Autodesk Fusion 360 part; units mm, degrees
(part 2 of 3)
sketch "Editable cross section (93)" plane through (0, 0, 0) normal (0, 0, 1) x (1, 0, 0) in component "right scoring bearing bridge 33"
  line L0 (-7.5, -5) -> (7.5, -5)
  line L1 (7.5, -5) -> (7.5, 5)
  line L2 (7.5, 5) -> (-7.5, 5)
  line L3 (-7.5, 5) -> (-7.5, -5)
extrude "Stock length''''''''''''''''''''''''''''''''''''''''''''''''''''''''''''''''''''''''''''''''''''''''''''" add sketch "Editable cross section (93)" along normal blind 42 separate body makes body 93 in component "right scoring bearing bridge 33"
sketch "Editable cross section (94)" plane through (0, 0, 0) normal (0, 0, 1) x (1, 0, 0) in component "left scoring wheel"
  circle A0 centre (0, 0) radius 32
extrude "Stock length'''''''''''''''''''''''''''''''''''''''''''''''''''''''''''''''''''''''''''''''''''''''''''''" add sketch "Editable cross section (94)" along normal blind 50 separate body makes body 94 in component "left scoring wheel"
sketch "Editable cross section (95)" plane through (0, 0, 0) normal (0, 0, 1) x (1, 0, 0) in component "left scoring spindle"
  circle A0 centre (0, 0) radius 6
extrude "Stock length''''''''''''''''''''''''''''''''''''''''''''''''''''''''''''''''''''''''''''''''''''''''''''''" add sketch "Editable cross section (95)" along normal blind 72 separate body makes body 95 in component "left scoring spindle"
sketch "Editable cross section (96)" plane through (0, 0, 0) normal (0, 0, 1) x (1, 0, 0) in component "left upper guide"
  line L0 (-3, -5) -> (3, -5)
  line L1 (3, -5) -> (3, 5)
  line L2 (3, 5) -> (-3, 5)
  line L3 (-3, 5) -> (-3, -5)
extrude "Stock length'''''''''''''''''''''''''''''''''''''''''''''''''''''''''''''''''''''''''''''''''''''''''''''''" add sketch "Editable cross section (96)" along normal blind 203.3249 separate body makes body 96 in component "left upper guide"
sketch "Editable cross section (97)" plane through (0, 0, 0) normal (0, 0, 1) x (1, 0, 0) in component "left scoring bearing bridge -33"
  line L0 (-7.5, -5) -> (7.5, -5)
  line L1 (7.5, -5) -> (7.5, 5)
  line L2 (7.5, 5) -> (-7.5, 5)
  line L3 (-7.5, 5) -> (-7.5, -5)
extrude "Stock length''''''''''''''''''''''''''''''''''''''''''''''''''''''''''''''''''''''''''''''''''''''''''''''''" add sketch "Editable cross section (97)" along normal blind 42 separate body makes body 97 in component "left scoring bearing bridge -33"
sketch "Editable cross section (98)" plane through (0, 0, 0) normal (0, 0, 1) x (1, 0, 0) in component "left scoring bearing bridge 33"
  line L0 (-7.5, -5) -> (7.5, -5)
  line L1 (7.5, -5) -> (7.5, 5)
  line L2 (7.5, 5) -> (-7.5, 5)
  line L3 (-7.5, 5) -> (-7.5, -5)
extrude "Stock length'''''''''''''''''''''''''''''''''''''''''''''''''''''''''''''''''''''''''''''''''''''''''''''''''" add sketch "Editable cross section (98)" along normal blind 42 separate body makes body 98 in component "left scoring bearing bridge 33"
sketch "Editable cross section (99)" plane through (0, 0, 0) normal (0, 0, 1) x (1, 0, 0) in component "left feed diverter pivot"
  circle A0 centre (0, 0) radius 7
extrude "Stock length''''''''''''''''''''''''''''''''''''''''''''''''''''''''''''''''''''''''''''''''''''''''''''''''''" add sketch "Editable cross section (99)" along normal blind 24 separate body makes body 99 in component "left feed diverter pivot"
sketch "Editable cross section (100)" plane through (0, 0, 0) normal (0, 0, 1) x (1, 0, 0) in component "right feed diverter pivot"
  circle A0 centre (0, 0) radius 7
extrude "Stock length'''''''''''''''''''''''''''''''''''''''''''''''''''''''''''''''''''''''''''''''''''''''''''''''''''" add sketch "Editable cross section (100)" along normal blind 24 separate body makes body 100 in component "right feed diverter pivot"
sketch "Editable cross section (101)" plane through (0, 0, 0) normal (0, 0, 1) x (1, 0, 0) in component "feed diverter vane"
  line L0 (-2, -75) -> (2, -75)
  line L1 (2, -75) -> (2, 75)
  line L2 (2, 75) -> (-2, 75)
  line L3 (-2, 75) -> (-2, -75)
extrude "Stock length''''''''''''''''''''''''''''''''''''''''''''''''''''''''''''''''''''''''''''''''''''''''''''''''''''" add sketch "Editable cross section (101)" along normal blind 46 separate body makes body 101 in component "feed diverter vane"
sketch "Editable cross section (102)" plane through (0, 0, 0) normal (0, 0, 1) x (1, 0, 0) in component "front left public wheel"
  circle A0 centre (0, 0) radius 38.1
extrude "Stock length'''''''''''''''''''''''''''''''''''''''''''''''''''''''''''''''''''''''''''''''''''''''''''''''''''''" add sketch "Editable cross section (102)" along normal blind 26 separate body makes body 102 in component "front left public wheel"
sketch "Editable cross section (103)" plane through (0, 0, 0) normal (0, 0, 1) x (1, 0, 0) in component "front left public drive housing"
  line L0 (-40, -40) -> (40, -40)
  line L1 (40, -40) -> (40, 40)
  line L2 (40, 40) -> (-40, 40)
  line L3 (-40, 40) -> (-40, -40)
extrude "Stock length''''''''''''''''''''''''''''''''''''''''''''''''''''''''''''''''''''''''''''''''''''''''''''''''''''''" add sketch "Editable cross section (103)" along normal blind 45 separate body makes body 103 in component "front left public drive housing"
sketch "Editable cross section (104)" plane through (0, 0, 0) normal (0, 0, 1) x (1, 0, 0) in component "front left public motor reserve"
  circle A0 centre (0, 0) radius 29.9
extrude "Stock length'''''''''''''''''''''''''''''''''''''''''''''''''''''''''''''''''''''''''''''''''''''''''''''''''''''''" add sketch "Editable cross section (104)" along normal blind 56.46 separate body makes body 104 in component "front left public motor reserve"
sketch "Editable cross section (105)" plane through (0, 0, 0) normal (0, 0, 1) x (1, 0, 0) in component "front right public wheel"
  circle A0 centre (0, 0) radius 38.1
extrude "Stock length''''''''''''''''''''''''''''''''''''''''''''''''''''''''''''''''''''''''''''''''''''''''''''''''''''''''" add sketch "Editable cross section (105)" along normal blind 26 separate body makes body 105 in component "front right public wheel"
sketch "Editable cross section (106)" plane through (0, 0, 0) normal (0, 0, 1) x (1, 0, 0) in component "front right public drive housing"
  line L0 (-40, -40) -> (40, -40)
  line L1 (40, -40) -> (40, 40)
  line L2 (40, 40) -> (-40, 40)
  line L3 (-40, 40) -> (-40, -40)
extrude "Stock length'''''''''''''''''''''''''''''''''''''''''''''''''''''''''''''''''''''''''''''''''''''''''''''''''''''''''" add sketch "Editable cross section (106)" along normal blind 45 separate body makes body 106 in component "front right public drive housing"
sketch "Editable cross section (107)" plane through (0, 0, 0) normal (0, 0, 1) x (1, 0, 0) in component "front right public motor reserve"
  circle A0 centre (0, 0) radius 29.9
extrude "Stock length''''''''''''''''''''''''''''''''''''''''''''''''''''''''''''''''''''''''''''''''''''''''''''''''''''''''''" add sketch "Editable cross section (107)" along normal blind 56.46 separate body makes body 107 in component "front right public motor reserve"
sketch "Editable cross section (108)" plane through (0, 0, 0) normal (0, 0, 1) x (1, 0, 0) in component "rear left public wheel"
  circle A0 centre (0, 0) radius 38.1
extrude "Stock length'''''''''''''''''''''''''''''''''''''''''''''''''''''''''''''''''''''''''''''''''''''''''''''''''''''''''''" add sketch "Editable cross section (108)" along normal blind 26 separate body makes body 108 in component "rear left public wheel"
sketch "Editable cross section (109)" plane through (0, 0, 0) normal (0, 0, 1) x (1, 0, 0) in component "rear left public drive housing"
  line L0 (-40, -40) -> (40, -40)
  line L1 (40, -40) -> (40, 40)
  line L2 (40, 40) -> (-40, 40)
  line L3 (-40, 40) -> (-40, -40)
extrude "Stock length''''''''''''''''''''''''''''''''''''''''''''''''''''''''''''''''''''''''''''''''''''''''''''''''''''''''''''" add sketch "Editable cross section (109)" along normal blind 45 separate body makes body 109 in component "rear left public drive housing"
sketch "Editable cross section (110)" plane through (0, 0, 0) normal (0, 0, 1) x (1, 0, 0) in component "rear left public motor reserve"
  circle A0 centre (0, 0) radius 29.9
extrude "Stock length'''''''''''''''''''''''''''''''''''''''''''''''''''''''''''''''''''''''''''''''''''''''''''''''''''''''''''''" add sketch "Editable cross section (110)" along normal blind 56.46 separate body makes body 110 in component "rear left public motor reserve"
sketch "Editable cross section (111)" plane through (0, 0, 0) normal (0, 0, 1) x (1, 0, 0) in component "rear right public wheel"
  circle A0 centre (0, 0) radius 38.1
extrude "Stock length''''''''''''''''''''''''''''''''''''''''''''''''''''''''''''''''''''''''''''''''''''''''''''''''''''''''''''''" add sketch "Editable cross section (111)" along normal blind 26 separate body makes body 111 in component "rear right public wheel"
sketch "Editable cross section (112)" plane through (0, 0, 0) normal (0, 0, 1) x (1, 0, 0) in component "rear right public drive housing"
  line L0 (-40, -40) -> (40, -40)
  line L1 (40, -40) -> (40, 40)
  line L2 (40, 40) -> (-40, 40)
  line L3 (-40, 40) -> (-40, -40)
extrude "Stock length'''''''''''''''''''''''''''''''''''''''''''''''''''''''''''''''''''''''''''''''''''''''''''''''''''''''''''''''" add sketch "Editable cross section (112)" along normal blind 45 separate body makes body 112 in component "rear right public drive housing"
sketch "Editable cross section (113)" plane through (0, 0, 0) normal (0, 0, 1) x (1, 0, 0) in component "rear right public motor reserve"
  circle A0 centre (0, 0) radius 29.9
extrude "Stock length''''''''''''''''''''''''''''''''''''''''''''''''''''''''''''''''''''''''''''''''''''''''''''''''''''''''''''''''" add sketch "Editable cross section (113)" along normal blind 56.46 separate body makes body 113 in component "rear right public motor reserve"
sketch "Editable cross section (114)" plane through (0, 0, 0) normal (0, 0, 1) x (1, 0, 0) in component "right public scoring motor envelope"
  circle A0 centre (0, 0) radius 30
extrude "Stock length'''''''''''''''''''''''''''''''''''''''''''''''''''''''''''''''''''''''''''''''''''''''''''''''''''''''''''''''''" add sketch "Editable cross section (114)" along normal blind 93.26 separate body makes body 114 in component "right public scoring motor envelope"
sketch "Editable cross section (115)" plane through (0, 0, 0) normal (0, 0, 1) x (1, 0, 0) in component "left public scoring motor envelope"
  circle A0 centre (0, 0) radius 30
extrude "Stock length''''''''''''''''''''''''''''''''''''''''''''''''''''''''''''''''''''''''''''''''''''''''''''''''''''''''''''''''''" add sketch "Editable cross section (115)" along normal blind 93.26 separate body makes body 115 in component "left public scoring motor envelope"
sketch "Editable cross section (116)" plane through (0, 0, 0) normal (0, 0, 1) x (1, 0, 0) in component "rear lift custody gate"
  line L0 (-2, -65) -> (2, -65)
  line L1 (2, -65) -> (2, 65)
  line L2 (2, 65) -> (-2, 65)
  line L3 (-2, 65) -> (-2, -65)
extrude "Stock length'''''''''''''''''''''''''''''''''''''''''''''''''''''''''''''''''''''''''''''''''''''''''''''''''''''''''''''''''''" add sketch "Editable cross section (116)" along normal blind 416 separate body makes body 116 in component "rear lift custody gate"
sketch "Editable cross section (117)" plane through (0, 0, 0) normal (0, 0, 1) x (1, 0, 0) in component "front lift custody guide"
  line L0 (-2, -65) -> (2, -65)
  line L1 (2, -65) -> (2, 65)
  line L2 (2, 65) -> (-2, 65)
  line L3 (-2, 65) -> (-2, -65)
extrude "Stock length''''''''''''''''''''''''''''''''''''''''''''''''''''''''''''''''''''''''''''''''''''''''''''''''''''''''''''''''''''" add sketch "Editable cross section (117)" along normal blind 361 separate body makes body 117 in component "front lift custody guide"
sketch "Editable cross section (118)" plane through (0, 0, 0) normal (0, 0, 1) x (1, 0, 0) in component "left mast"
  line L0 (-10, -10) -> (10, -10)
  line L1 (10, -10) -> (10, 10)
  line L2 (10, 10) -> (-10, 10)
  line L3 (-10, 10) -> (-10, -10)
  line L4 (-8, -8) -> (8, -8)
  line L5 (8, -8) -> (8, 8)
  line L6 (8, 8) -> (-8, 8)
  line L7 (-8, 8) -> (-8, -8)
extrude "Stock length'''''''''''''''''''''''''''''''''''''''''''''''''''''''''''''''''''''''''''''''''''''''''''''''''''''''''''''''''''''" add sketch "Editable cross section (118)" along normal blind 629.2 separate body makes body 118 in component "left mast"
sketch "Editable cross section (119)" plane through (0, 0, 0) normal (0, 0, 1) x (1, 0, 0) in component "left aft mast"
  line L0 (-10, -10) -> (10, -10)
  line L1 (10, -10) -> (10, 10)
  line L2 (10, 10) -> (-10, 10)
  line L3 (-10, 10) -> (-10, -10)
  line L4 (-8, -8) -> (8, -8)
  line L5 (8, -8) -> (8, 8)
  line L6 (8, 8) -> (-8, 8)
  line L7 (-8, 8) -> (-8, -8)
extrude "Stock length''''''''''''''''''''''''''''''''''''''''''''''''''''''''''''''''''''''''''''''''''''''''''''''''''''''''''''''''''''''" add sketch "Editable cross section (119)" along normal blind 629.2 separate body makes body 119 in component "left aft mast"
sketch "Editable cross section (120)" plane through (0, 0, 0) normal (0, 0, 1) x (1, 0, 0) in component "left upper bearing plate"
  line L0 (-64, -19) -> (64, -19)
  line L1 (64, -19) -> (64, 19)
  line L2 (64, 19) -> (-64, 19)
  line L3 (-64, 19) -> (-64, -19)
extrude "Stock length'''''''''''''''''''''''''''''''''''''''''''''''''''''''''''''''''''''''''''''''''''''''''''''''''''''''''''''''''''''''" add sketch "Editable cross section (120)" along normal blind 6 separate body makes body 120 in component "left upper bearing plate"
sketch "Editable cross section (121)" plane through (0, 0, 0) normal (0, 0, 1) x (1, 0, 0) in component "left lower bearing plate"
  line L0 (-27, -21.5) -> (27, -21.5)
  line L1 (27, -21.5) -> (27, 21.5)
  line L2 (27, 21.5) -> (-27, 21.5)
  line L3 (-27, 21.5) -> (-27, -21.5)
extrude "Stock length''''''''''''''''''''''''''''''''''''''''''''''''''''''''''''''''''''''''''''''''''''''''''''''''''''''''''''''''''''''''" add sketch "Editable cross section (121)" along normal blind 6 separate body makes body 121 in component "left lower bearing plate"
sketch "Editable cross section (122)" plane through (0, 0, 0) normal (0, 0, 1) x (1, 0, 0) in component "left lead screw envelope"
  circle A0 centre (0, 0) radius 5
extrude "Stock length'''''''''''''''''''''''''''''''''''''''''''''''''''''''''''''''''''''''''''''''''''''''''''''''''''''''''''''''''''''''''" add sketch "Editable cross section (122)" along normal blind 187 separate body makes body 122 in component "left lead screw envelope"
sketch "Editable cross section (123)" plane through (0, 0, 0) normal (0, 0, 1) x (1, 0, 0) in component "left lift motor envelope"
  circle A0 centre (0, 0) radius 30
extrude "Stock length''''''''''''''''''''''''''''''''''''''''''''''''''''''''''''''''''''''''''''''''''''''''''''''''''''''''''''''''''''''''''" add sketch "Editable cross section (123)" along normal blind 61 separate body makes body 123 in component "left lift motor envelope"
sketch "Editable cross section (124)" plane through (0, 0, 0) normal (0, 0, 1) x (1, 0, 0) in component "left reduction envelope"
  line L0 (-19, -32) -> (19, -32)
  line L1 (19, -32) -> (19, 32)
  line L2 (19, 32) -> (-19, 32)
  line L3 (-19, 32) -> (-19, -32)
extrude "Stock length'''''''''''''''''''''''''''''''''''''''''''''''''''''''''''''''''''''''''''''''''''''''''''''''''''''''''''''''''''''''''''" add sketch "Editable cross section (124)" along normal blind 20 separate body makes body 124 in component "left reduction envelope"
sketch "Editable cross section (125)" plane through (0, 0, 0) normal (0, 0, 1) x (1, 0, 0) in component "left driven nut"
  line L0 (-9, -9.5) -> (9, -9.5)
  line L1 (9, -9.5) -> (9, 9.5)
  line L2 (9, 9.5) -> (-9, 9.5)
  line L3 (-9, 9.5) -> (-9, -9.5)
  circle A0 centre (0, -0.5) radius 5
extrude "Stock length''''''''''''''''''''''''''''''''''''''''''''''''''''''''''''''''''''''''''''''''''''''''''''''''''''''''''''''''''''''''''''" add sketch "Editable cross section (125)" along normal blind 14 separate body makes body 125 in component "left driven nut"
sketch "Editable cross section (126)" plane through (0, 0, 0) normal (0, 0, 1) x (1, 0, 0) in component "left nut link"
  line L0 (-8, -8) -> (8, -8)
  line L1 (8, -8) -> (8, 8)
  line L2 (8, 8) -> (-8, 8)
  line L3 (-8, 8) -> (-8, -8)
  circle A0 centre (0, -1) radius 5.8
extrude "Stock length'''''''''''''''''''''''''''''''''''''''''''''''''''''''''''''''''''''''''''''''''''''''''''''''''''''''''''''''''''''''''''''" add sketch "Editable cross section (126)" along normal blind 10 separate body makes body 126 in component "left nut link"
sketch "Editable cross section (127)" plane through (0, 0, 0) normal (0, 0, 1) x (1, 0, 0) in component "left crosshead cheek"
  line L0 (-87.5, -11.5) -> (87.5, -11.5)
  line L1 (87.5, -11.5) -> (87.5, 11.5)
  line L2 (87.5, 11.5) -> (-87.5, 11.5)
  line L3 (-87.5, 11.5) -> (-87.5, -11.5)
  circle A0 centre (-35.5, 1.5) radius 5.8
extrude "Stock length''''''''''''''''''''''''''''''''''''''''''''''''''''''''''''''''''''''''''''''''''''''''''''''''''''''''''''''''''''''''''''''" add sketch "Editable cross section (127)" along normal blind 14 separate body makes body 127 in component "left crosshead cheek"
sketch "Editable cross section (128)" plane through (0, 0, 0) normal (0, 0, 1) x (1, 0, 0) in component "left forward carriage sleeve"
  line L0 (-13, -12.5) -> (13, -12.5)
  line L1 (13, -12.5) -> (13, 12.5)
  line L2 (13, 12.5) -> (-13, 12.5)
  line L3 (-13, 12.5) -> (-13, -12.5)
  line L4 (-11, -10.5) -> (11, -10.5)
  line L5 (11, -10.5) -> (11, 10.5)
  line L6 (11, 10.5) -> (-11, 10.5)
  line L7 (-11, 10.5) -> (-11, -10.5)
extrude "Stock length'''''''''''''''''''''''''''''''''''''''''''''''''''''''''''''''''''''''''''''''''''''''''''''''''''''''''''''''''''''''''''''''" add sketch "Editable cross section (128)" along normal blind 40 separate body makes body 128 in component "left forward carriage sleeve"
sketch "Editable cross section (129)" plane through (0, 0, 0) normal (0, 0, 1) x (1, 0, 0) in component "left aft carriage sleeve"
  line L0 (-13, -12.5) -> (13, -12.5)
  line L1 (13, -12.5) -> (13, 12.5)
  line L2 (13, 12.5) -> (-13, 12.5)
  line L3 (-13, 12.5) -> (-13, -12.5)
  line L4 (-11, -10.5) -> (11, -10.5)
  line L5 (11, -10.5) -> (11, 10.5)
  line L6 (11, 10.5) -> (-11, 10.5)
  line L7 (-11, 10.5) -> (-11, -10.5)
extrude "Stock length''''''''''''''''''''''''''''''''''''''''''''''''''''''''''''''''''''''''''''''''''''''''''''''''''''''''''''''''''''''''''''''''" add sketch "Editable cross section (129)" along normal blind 40 separate body makes body 129 in component "left aft carriage sleeve"
sketch "Editable cross section (130)" plane through (0, 0, 0) normal (0, 0, 1) x (1, 0, 0) in component "left extension sleeve"
  line L0 (-14, -15) -> (14, -15)
  line L1 (14, -15) -> (14, 15)
  line L2 (14, 15) -> (-14, 15)
  line L3 (-14, 15) -> (-14, -15)
  line L4 (-12, -13) -> (12, -13)
  line L5 (12, -13) -> (12, 13)
  line L6 (12, 13) -> (-12, 13)
  line L7 (-12, 13) -> (-12, -13)
extrude "Stock length'''''''''''''''''''''''''''''''''''''''''''''''''''''''''''''''''''''''''''''''''''''''''''''''''''''''''''''''''''''''''''''''''" add sketch "Editable cross section (130)" along normal blind 87 separate body makes body 130 in component "left extension sleeve"
sketch "Editable cross section (131)" plane through (0, 0, 0) normal (0, 0, 1) x (1, 0, 0) in component "left sleeve pedestal"
  line L0 (-11, -11) -> (11, -11)
  line L1 (11, -11) -> (11, 11)
  line L2 (11, 11) -> (-11, 11)
  line L3 (-11, 11) -> (-11, -11)
extrude "Stock length''''''''''''''''''''''''''''''''''''''''''''''''''''''''''''''''''''''''''''''''''''''''''''''''''''''''''''''''''''''''''''''''''" add sketch "Editable cross section (131)" along normal blind 23 separate body makes body 131 in component "left sleeve pedestal"
sketch "Editable cross section (132)" plane through (0, 0, 0) normal (0, 0, 1) x (1, 0, 0) in component "left extending rail"
  line L0 (-10, -11) -> (10, -11)
  line L1 (10, -11) -> (10, 11)
  line L2 (10, 11) -> (-10, 11)
  line L3 (-10, 11) -> (-10, -11)
  line L4 (-8, -9) -> (8, -9)
  line L5 (8, -9) -> (8, 9)
  line L6 (8, 9) -> (-8, 9)
  line L7 (-8, 9) -> (-8, -9)
extrude "Stock length'''''''''''''''''''''''''''''''''''''''''''''''''''''''''''''''''''''''''''''''''''''''''''''''''''''''''''''''''''''''''''''''''''" add sketch "Editable cross section (132)" along normal blind 395 separate body makes body 132 in component "left extending rail"
sketch "Low-rung crown and capture slot" plane through (0, 0, 0) normal (0, 0, 1) x (1, 0, 0) in component "left crown hook"
  line L0 (-283, 710) -> (-271, 710)
  line L1 (-271, 710) -> (-271, 737)
  line L2 (-271, 737) -> (-223, 737)
  line L3 (-223, 737) -> (-223, 710)
  line L4 (-223, 710) -> (-211, 710)
  line L5 (-211, 710) -> (-211, 736)
  line L6 (-211, 736) -> (-176, 736)
  line L7 (-176, 736) -> (-176, 753)
  line L8 (-176, 753) -> (-283, 753)
  line L9 (-283, 753) -> (-283, 710)
extrude "Hook plate thickness" add sketch "Low-rung crown and capture slot" along normal blind 12 separate body makes body 133 in component "left crown hook"
sketch "Editable cross section (133)" plane through (0, 0, 0) normal (0, 0, 1) x (1, 0, 0) in component "right mast"
  line L0 (-10, -10) -> (10, -10)
  line L1 (10, -10) -> (10, 10)
  line L2 (10, 10) -> (-10, 10)
  line L3 (-10, 10) -> (-10, -10)
  line L4 (-8, -8) -> (8, -8)
  line L5 (8, -8) -> (8, 8)
  line L6 (8, 8) -> (-8, 8)
  line L7 (-8, 8) -> (-8, -8)
extrude "Stock length''''''''''''''''''''''''''''''''''''''''''''''''''''''''''''''''''''''''''''''''''''''''''''''''''''''''''''''''''''''''''''''''''''" add sketch "Editable cross section (133)" along normal blind 629.2 separate body makes body 134 in component "right mast"
sketch "Editable cross section (134)" plane through (0, 0, 0) normal (0, 0, 1) x (1, 0, 0) in component "right aft mast"
  line L0 (-10, -10) -> (10, -10)
  line L1 (10, -10) -> (10, 10)
  line L2 (10, 10) -> (-10, 10)
  line L3 (-10, 10) -> (-10, -10)
  line L4 (-8, -8) -> (8, -8)
  line L5 (8, -8) -> (8, 8)
  line L6 (8, 8) -> (-8, 8)
  line L7 (-8, 8) -> (-8, -8)
extrude "Stock length'''''''''''''''''''''''''''''''''''''''''''''''''''''''''''''''''''''''''''''''''''''''''''''''''''''''''''''''''''''''''''''''''''''" add sketch "Editable cross section (134)" along normal blind 629.2 separate body makes body 135 in component "right aft mast"
sketch "Editable cross section (135)" plane through (0, 0, 0) normal (0, 0, 1) x (1, 0, 0) in component "right upper bearing plate"
  line L0 (-64, -19) -> (64, -19)
  line L1 (64, -19) -> (64, 19)
  line L2 (64, 19) -> (-64, 19)
  line L3 (-64, 19) -> (-64, -19)
extrude "Stock length''''''''''''''''''''''''''''''''''''''''''''''''''''''''''''''''''''''''''''''''''''''''''''''''''''''''''''''''''''''''''''''''''''''" add sketch "Editable cross section (135)" along normal blind 6 separate body makes body 136 in component "right upper bearing plate"
sketch "Editable cross section (136)" plane through (0, 0, 0) normal (0, 0, 1) x (1, 0, 0) in component "right lower bearing plate"
  line L0 (-27, -21.5) -> (27, -21.5)
  line L1 (27, -21.5) -> (27, 21.5)
  line L2 (27, 21.5) -> (-27, 21.5)
  line L3 (-27, 21.5) -> (-27, -21.5)
extrude "Stock length'''''''''''''''''''''''''''''''''''''''''''''''''''''''''''''''''''''''''''''''''''''''''''''''''''''''''''''''''''''''''''''''''''''''" add sketch "Editable cross section (136)" along normal blind 6 separate body makes body 137 in component "right lower bearing plate"
sketch "Editable cross section (137)" plane through (0, 0, 0) normal (0, 0, 1) x (1, 0, 0) in component "right lead screw envelope"
  circle A0 centre (0, 0) radius 5
extrude "Stock length''''''''''''''''''''''''''''''''''''''''''''''''''''''''''''''''''''''''''''''''''''''''''''''''''''''''''''''''''''''''''''''''''''''''" add sketch "Editable cross section (137)" along normal blind 187 separate body makes body 138 in component "right lead screw envelope"
sketch "Editable cross section (138)" plane through (0, 0, 0) normal (0, 0, 1) x (1, 0, 0) in component "right lift motor envelope"
  circle A0 centre (0, 0) radius 30
extrude "Stock length'''''''''''''''''''''''''''''''''''''''''''''''''''''''''''''''''''''''''''''''''''''''''''''''''''''''''''''''''''''''''''''''''''''''''" add sketch "Editable cross section (138)" along normal blind 61 separate body makes body 139 in component "right lift motor envelope"
sketch "Editable cross section (139)" plane through (0, 0, 0) normal (0, 0, 1) x (1, 0, 0) in component "right reduction envelope"
  line L0 (-19, -32) -> (19, -32)
  line L1 (19, -32) -> (19, 32)
  line L2 (19, 32) -> (-19, 32)
  line L3 (-19, 32) -> (-19, -32)
extrude "Stock length''''''''''''''''''''''''''''''''''''''''''''''''''''''''''''''''''''''''''''''''''''''''''''''''''''''''''''''''''''''''''''''''''''''''''" add sketch "Editable cross section (139)" along normal blind 20 separate body makes body 140 in component "right reduction envelope"
sketch "Editable cross section (140)" plane through (0, 0, 0) normal (0, 0, 1) x (1, 0, 0) in component "right driven nut"
  line L0 (-9, -9.5) -> (9, -9.5)
  line L1 (9, -9.5) -> (9, 9.5)
  line L2 (9, 9.5) -> (-9, 9.5)
  line L3 (-9, 9.5) -> (-9, -9.5)
  circle A0 centre (0, 0.5) radius 5
extrude "Stock length'''''''''''''''''''''''''''''''''''''''''''''''''''''''''''''''''''''''''''''''''''''''''''''''''''''''''''''''''''''''''''''''''''''''''''" add sketch "Editable cross section (140)" along normal blind 14 separate body makes body 141 in component "right driven nut"
sketch "Editable cross section (141)" plane through (0, 0, 0) normal (0, 0, 1) x (1, 0, 0) in component "right nut link"
  line L0 (-8, -8) -> (8, -8)
  line L1 (8, -8) -> (8, 8)
  line L2 (8, 8) -> (-8, 8)
  line L3 (-8, 8) -> (-8, -8)
  circle A0 centre (0, 1) radius 5.8
extrude "Stock length''''''''''''''''''''''''''''''''''''''''''''''''''''''''''''''''''''''''''''''''''''''''''''''''''''''''''''''''''''''''''''''''''''''''''''" add sketch "Editable cross section (141)" along normal blind 10 separate body makes body 142 in component "right nut link"
sketch "Editable cross section (142)" plane through (0, 0, 0) normal (0, 0, 1) x (1, 0, 0) in component "right crosshead cheek"
  line L0 (-87.5, -11.5) -> (87.5, -11.5)
  line L1 (87.5, -11.5) -> (87.5, 11.5)
  line L2 (87.5, 11.5) -> (-87.5, 11.5)
  line L3 (-87.5, 11.5) -> (-87.5, -11.5)
  circle A0 centre (-35.5, -1.5) radius 5.8
extrude "Stock length'''''''''''''''''''''''''''''''''''''''''''''''''''''''''''''''''''''''''''''''''''''''''''''''''''''''''''''''''''''''''''''''''''''''''''''" add sketch "Editable cross section (142)" along normal blind 14 separate body makes body 143 in component "right crosshead cheek"
sketch "Editable cross section (143)" plane through (0, 0, 0) normal (0, 0, 1) x (1, 0, 0) in component "right forward carriage sleeve"
  line L0 (-13, -12.5) -> (13, -12.5)
  line L1 (13, -12.5) -> (13, 12.5)
  line L2 (13, 12.5) -> (-13, 12.5)
  line L3 (-13, 12.5) -> (-13, -12.5)
  line L4 (-11, -10.5) -> (11, -10.5)
  line L5 (11, -10.5) -> (11, 10.5)
  line L6 (11, 10.5) -> (-11, 10.5)
  line L7 (-11, 10.5) -> (-11, -10.5)
extrude "Stock length''''''''''''''''''''''''''''''''''''''''''''''''''''''''''''''''''''''''''''''''''''''''''''''''''''''''''''''''''''''''''''''''''''''''''''''" add sketch "Editable cross section (143)" along normal blind 40 separate body makes body 144 in component "right forward carriage sleeve"
sketch "Editable cross section (144)" plane through (0, 0, 0) normal (0, 0, 1) x (1, 0, 0) in component "right aft carriage sleeve"
  line L0 (-13, -12.5) -> (13, -12.5)
  line L1 (13, -12.5) -> (13, 12.5)
  line L2 (13, 12.5) -> (-13, 12.5)
  line L3 (-13, 12.5) -> (-13, -12.5)
  line L4 (-11, -10.5) -> (11, -10.5)
  line L5 (11, -10.5) -> (11, 10.5)
  line L6 (11, 10.5) -> (-11, 10.5)
  line L7 (-11, 10.5) -> (-11, -10.5)
extrude "Stock length'''''''''''''''''''''''''''''''''''''''''''''''''''''''''''''''''''''''''''''''''''''''''''''''''''''''''''''''''''''''''''''''''''''''''''''''" add sketch "Editable cross section (144)" along normal blind 40 separate body makes body 145 in component "right aft carriage sleeve"
sketch "Editable cross section (145)" plane through (0, 0, 0) normal (0, 0, 1) x (1, 0, 0) in component "right extension sleeve"
  line L0 (-14, -15) -> (14, -15)
  line L1 (14, -15) -> (14, 15)
  line L2 (14, 15) -> (-14, 15)
  line L3 (-14, 15) -> (-14, -15)
  line L4 (-12, -13) -> (12, -13)
  line L5 (12, -13) -> (12, 13)
  line L6 (12, 13) -> (-12, 13)
  line L7 (-12, 13) -> (-12, -13)
extrude "Stock length''''''''''''''''''''''''''''''''''''''''''''''''''''''''''''''''''''''''''''''''''''''''''''''''''''''''''''''''''''''''''''''''''''''''''''''''" add sketch "Editable cross section (145)" along normal blind 87 separate body makes body 146 in component "right extension sleeve"
sketch "Editable cross section (146)" plane through (0, 0, 0) normal (0, 0, 1) x (1, 0, 0) in component "right sleeve pedestal"
  line L0 (-11, -11) -> (11, -11)
  line L1 (11, -11) -> (11, 11)
  line L2 (11, 11) -> (-11, 11)
  line L3 (-11, 11) -> (-11, -11)
extrude "Stock length'''''''''''''''''''''''''''''''''''''''''''''''''''''''''''''''''''''''''''''''''''''''''''''''''''''''''''''''''''''''''''''''''''''''''''''''''" add sketch "Editable cross section (146)" along normal blind 23 separate body makes body 147 in component "right sleeve pedestal"
sketch "Editable cross section (147)" plane through (0, 0, 0) normal (0, 0, 1) x (1, 0, 0) in component "right extending rail"
  line L0 (-10, -11) -> (10, -11)
  line L1 (10, -11) -> (10, 11)
  line L2 (10, 11) -> (-10, 11)
  line L3 (-10, 11) -> (-10, -11)
  line L4 (-8, -9) -> (8, -9)
  line L5 (8, -9) -> (8, 9)
  line L6 (8, 9) -> (-8, 9)
  line L7 (-8, 9) -> (-8, -9)
extrude "Stock length''''''''''''''''''''''''''''''''''''''''''''''''''''''''''''''''''''''''''''''''''''''''''''''''''''''''''''''''''''''''''''''''''''''''''''''''''" add sketch "Editable cross section (147)" along normal blind 395 separate body makes body 148 in component "right extending rail"
sketch "Low-rung crown and capture slot (2)" plane through (0, 0, 0) normal (0, 0, 1) x (1, 0, 0) in component "right crown hook"
  line L0 (-283, 710) -> (-271, 710)
  line L1 (-271, 710) -> (-271, 737)
  line L2 (-271, 737) -> (-223, 737)
  line L3 (-223, 737) -> (-223, 710)
  line L4 (-223, 710) -> (-211, 710)
  line L5 (-211, 710) -> (-211, 736)
  line L6 (-211, 736) -> (-176, 736)
  line L7 (-176, 736) -> (-176, 753)
  line L8 (-176, 753) -> (-283, 753)
  line L9 (-283, 753) -> (-283, 710)
extrude "Hook plate thickness'" add sketch "Low-rung crown and capture slot (2)" along normal blind 12 separate body makes body 149 in component "right crown hook"
sketch "Editable cross section (148)" plane through (0, 0, 0) normal (0, 0, 1) x (1, 0, 0) in component "crosshead lift bridge"
  line L0 (-10, -10) -> (10, -10)
  line L1 (10, -10) -> (10, 10)
  line L2 (10, 10) -> (-10, 10)
  line L3 (-10, 10) -> (-10, -10)
  line L4 (-8, -8) -> (8, -8)
  line L5 (8, -8) -> (8, 8)
  line L6 (8, 8) -> (-8, 8)
  line L7 (-8, 8) -> (-8, -8)
extrude "Stock length'''''''''''''''''''''''''''''''''''''''''''''''''''''''''''''''''''''''''''''''''''''''''''''''''''''''''''''''''''''''''''''''''''''''''''''''''''" add sketch "Editable cross section (148)" along normal blind 630 separate body makes body 150 in component "crosshead lift bridge"
sketch "Editable cross section (149)" plane through (0, 0, 0) normal (0, 0, 1) x (1, 0, 0) in component "rail synchronizing tie"
  line L0 (-10, -82) -> (10, -82)
  line L1 (10, -82) -> (10, 82)
  line L2 (10, 82) -> (-10, 82)
  line L3 (-10, 82) -> (-10, -82)
extrude "Stock length''''''''''''''''''''''''''''''''''''''''''''''''''''''''''''''''''''''''''''''''''''''''''''''''''''''''''''''''''''''''''''''''''''''''''''''''''''" add sketch "Editable cross section (149)" along normal blind 4 separate body makes body 151 in component "rail synchronizing tie"
sketch "Editable cross section (150)" plane through (0, 0, 0) normal (0, 0, 1) x (1, 0, 0) in component "extension bearing beam"
  line L0 (-193, -14) -> (193, -14)
  line L1 (193, -14) -> (193, 14)
  line L2 (193, 14) -> (-193, 14)
  line L3 (-193, 14) -> (-193, -14)
extrude "Stock length'''''''''''''''''''''''''''''''''''''''''''''''''''''''''''''''''''''''''''''''''''''''''''''''''''''''''''''''''''''''''''''''''''''''''''''''''''''" add sketch "Editable cross section (150)" along normal blind 15 separate body makes body 152 in component "extension bearing beam"
sketch "Editable cross section (151)" plane through (0, 0, 0) normal (0, 0, 1) x (1, 0, 0) in component "extension rear bearing and stop"
  line L0 (-14, -17) -> (14, -17)
  line L1 (14, -17) -> (14, 17)
  line L2 (14, 17) -> (-14, 17)
  line L3 (-14, 17) -> (-14, -17)
  circle A0 centre (0, 0) radius 5.2
extrude "Stock length''''''''''''''''''''''''''''''''''''''''''''''''''''''''''''''''''''''''''''''''''''''''''''''''''''''''''''''''''''''''''''''''''''''''''''''''''''''" add sketch "Editable cross section (151)" along normal blind 12 separate body makes body 153 in component "extension rear bearing and stop"
sketch "Editable cross section (152)" plane through (0, 0, 0) normal (0, 0, 1) x (1, 0, 0) in component "extension forward bearing"
  line L0 (-14, -17) -> (14, -17)
  line L1 (14, -17) -> (14, 17)
  line L2 (14, 17) -> (-14, 17)
  line L3 (-14, 17) -> (-14, -17)
  circle A0 centre (0, 0) radius 5.2
extrude "Stock length'''''''''''''''''''''''''''''''''''''''''''''''''''''''''''''''''''''''''''''''''''''''''''''''''''''''''''''''''''''''''''''''''''''''''''''''''''''''" add sketch "Editable cross section (152)" along normal blind 12 separate body makes body 154 in component "extension forward bearing"
sketch "Editable cross section (153)" plane through (0, 0, 0) normal (0, 0, 1) x (1, 0, 0) in component "extension screw envelope"
  circle A0 centre (0, 0) radius 5
extrude "Stock length''''''''''''''''''''''''''''''''''''''''''''''''''''''''''''''''''''''''''''''''''''''''''''''''''''''''''''''''''''''''''''''''''''''''''''''''''''''''" add sketch "Editable cross section (153)" along normal blind 279 separate body makes body 155 in component "extension screw envelope"
sketch "Editable cross section (154)" plane through (0, 0, 0) normal (0, 0, 1) x (1, 0, 0) in component "extension deployment nut"
  line L0 (-10, -13) -> (10, -13)
  line L1 (10, -13) -> (10, 13)
  line L2 (10, 13) -> (-10, 13)
  line L3 (-10, 13) -> (-10, -13)
  circle A0 centre (0, 0) radius 5
extrude "Stock length'''''''''''''''''''''''''''''''''''''''''''''''''''''''''''''''''''''''''''''''''''''''''''''''''''''''''''''''''''''''''''''''''''''''''''''''''''''''''" add sketch "Editable cross section (154)" along normal blind 20 separate body makes body 156 in component "extension deployment nut"
sketch "Editable cross section (155)" plane through (0, 0, 0) normal (0, 0, 1) x (1, 0, 0) in component "extension nut hanger"
  line L0 (-10, -8) -> (10, -8)
  line L1 (10, -8) -> (10, 8)
  line L2 (10, 8) -> (-10, 8)
  line L3 (-10, 8) -> (-10, -8)
extrude "Stock length''''''''''''''''''''''''''''''''''''''''''''''''''''''''''''''''''''''''''''''''''''''''''''''''''''''''''''''''''''''''''''''''''''''''''''''''''''''''''" add sketch "Editable cross section (155)" along normal blind 4 separate body makes body 157 in component "extension nut hanger"
sketch "Editable cross section (156)" plane through (0, 0, 0) normal (0, 0, 1) x (1, 0, 0) in component "extension motor envelope"
  circle A0 centre (0, 0) radius 18
extrude "Stock length'''''''''''''''''''''''''''''''''''''''''''''''''''''''''''''''''''''''''''''''''''''''''''''''''''''''''''''''''''''''''''''''''''''''''''''''''''''''''''" add sketch "Editable cross section (156)" along normal blind 49 separate body makes body 158 in component "extension motor envelope"
sketch "Editable cross section (157)" plane through (0, 0, 0) normal (0, 0, 1) x (1, 0, 0) in component "extension motor foot"
  line L0 (-8, -9) -> (8, -9)
  line L1 (8, -9) -> (8, 9)
  line L2 (8, 9) -> (-8, 9)
  line L3 (-8, 9) -> (-8, -9)
extrude "Stock length''''''''''''''''''''''''''''''''''''''''''''''''''''''''''''''''''''''''''''''''''''''''''''''''''''''''''''''''''''''''''''''''''''''''''''''''''''''''''''" add sketch "Editable cross section (157)" along normal blind 2 separate body makes body 159 in component "extension motor foot"
component "left perimeter tube" placed x (0, 1, 0) y (0, 0, 1) z (1, 0, 0) at (-340, 327.3, 89.4)
component "left front return" placed x (-1, 0, 0) y (0, 0, 1) z (0, 1, 0) at (327.3, 150, 89.4)
component "left blue side bumper" placed x (1, 0, 0) y (0, 1, 0) z (0, 0, 1) at (0, 378, 48)
component "left blue front bumper" placed x (1, 0, 0) y (0, 1, 0) z (0, 0, 1) at (378, 245, 48)
component "right perimeter tube" placed x (0, 1, 0) y (0, 0, 1) z (1, 0, 0) at (-340, -327.3, 89.4)
component "right front return" placed x (-1, 0, 0) y (0, 0, 1) z (0, 1, 0) at (327.3, -314.6, 89.4)
component "right blue side bumper" placed x (1, 0, 0) y (0, 1, 0) z (0, 0, 1) at (0, -378, 48)
component "right blue front bumper" placed x (1, 0, 0) y (0, 1, 0) z (0, 0, 1) at (378, -245, 48)
component "rear perimeter tube" placed x (-1, 0, 0) y (0, 0, 1) z (0, 1, 0) at (-327.3, -314.6, 89.4)
component "rear blue bumper" placed x (1, 0, 0) y (0, 1, 0) z (0, 0, 1) at (-378, 0, 48)
component "front left module tab spacer 1" placed x (1, 0, 0) y (0, 1, 0) z (0, 0, 1) at (198, 303.05, 78.32)
component "front left module tab spacer 2" placed x (1, 0, 0) y (0, 1, 0) z (0, 0, 1) at (303.05, 198, 78.32)
component "front right module tab spacer 1" placed x (1, 0, 0) y (0, 1, 0) z (0, 0, 1) at (303.05, -198, 78.32)
component "front right module tab spacer 2" placed x (1, 0, 0) y (0, 1, 0) z (0, 0, 1) at (198, -303.05, 78.32)
component "rear left module tab spacer 1" placed x (1, 0, 0) y (0, 1, 0) z (0, 0, 1) at (-303.05, 198, 78.32)
component "rear left module tab spacer 2" placed x (1, 0, 0) y (0, 1, 0) z (0, 0, 1) at (-198, 303.05, 78.32)
component "rear right module tab spacer 1" placed x (1, 0, 0) y (0, 1, 0) z (0, 0, 1) at (-198, -303.05, 78.32)
component "rear right module tab spacer 2" placed x (1, 0, 0) y (0, 1, 0) z (0, 0, 1) at (-303.05, -198, 78.32)
component "rear right hopper post" placed x (1, 0, 0) y (0, 1, 0) z (0, 0, 1) at (-188, -306, 115)
component "front right hopper post" placed x (1, 0, 0) y (0, 1, 0) z (0, 0, 1) at (176, -306, 115)
component "right floor sill" placed x (0, 1, 0) y (0, 0, 1) z (1, 0, 0) at (-330, -306, 227)
component "rear left hopper post" placed x (1, 0, 0) y (0, 1, 0) z (0, 0, 1) at (-188, 306, 115)
component "front left hopper post" placed x (1, 0, 0) y (0, 1, 0) z (0, 0, 1) at (176, 306, 115)
component "left floor sill" placed x (0, 1, 0) y (0, 0, 1) z (1, 0, 0) at (-330, 306, 227)
component "rear deck crossmember" placed x (-1, 0, 0) y (0, 0, 1) z (0, 1, 0) at (-188, -315, 113)
component "front deck crossmember" placed x (-1, 0, 0) y (0, 0, 1) z (0, 1, 0) at (176, -315, 113)
component "left electronics deck" placed x (1, 0, 0) y (0, 1, 0) z (0, 0, 1) at (-5.5, 149, 122)
component "right electronics deck" placed x (1, 0, 0) y (0, 1, 0) z (0, 0, 1) at (-5.5, -147.5, 122)
component "fore electronics deck bridge" placed x (1, 0, 0) y (0, 1, 0) z (0, 0, 1) at (110.5, 1.5, 122)
component "aft electronics deck bridge" placed x (1, 0, 0) y (0, 1, 0) z (0, 0, 1) at (-157.5, 1.5, 122)
component "battery cradle floor" placed x (1, 0, 0) y (0, 1, 0) z (0, 0, 1) at (-41.5, 1.5, 44)
component "battery cradle wall -44" placed x (1, 0, 0) y (0, 1, 0) z (0, 0, 1) at (-41.5, -42, 48)
component "battery cradle wall 43" placed x (1, 0, 0) y (0, 1, 0) z (0, 0, 1) at (-41.5, 45, 48)
component "battery secured envelope" placed x (1, 0, 0) y (0, 1, 0) z (0, 0, 1) at (-41.5, 2, 48)
component "distribution enclosure reserve" placed x (1, 0, 0) y (0, 1, 0) z (0, 0, 1) at (105, -3, 129)
component "robot controller reserve" placed x (1, 0, 0) y (0, 1, 0) z (0, 0, 1) at (-79.5, 108, 129)
component "field radio reserve" placed x (1, 0, 0) y (0, 1, 0) z (0, 0, 1) at (-88.5, -118.5, 129)
component "drive controller reserve 1" placed x (1, 0, 0) y (0, 1, 0) z (0, 0, 1) at (-120.5, -204, 129)
component "drive controller reserve 2" placed x (1, 0, 0) y (0, 1, 0) z (0, 0, 1) at (-120.5, 204, 129)
component "drive controller reserve 3" placed x (1, 0, 0) y (0, 1, 0) z (0, 0, 1) at (-42.5, -204, 129)
component "drive controller reserve 4" placed x (1, 0, 0) y (0, 1, 0) z (0, 0, 1) at (-42.5, 204, 129)
component "drive controller reserve 5" placed x (1, 0, 0) y (0, 1, 0) z (0, 0, 1) at (35.5, -204, 129)
component "drive controller reserve 6" placed x (1, 0, 0) y (0, 1, 0) z (0, 0, 1) at (35.5, 204, 129)
component "drive controller reserve 7" placed x (1, 0, 0) y (0, 1, 0) z (0, 0, 1) at (113.5, -204, 129)
component "drive controller reserve 8" placed x (1, 0, 0) y (0, 1, 0) z (0, 0, 1) at (113.5, 204, 129)
component "hopper back panel" placed x (1, 0, 0) y (0, 1, 0) z (0, 0, 1) at (-332, 0, 232)
component "right hopper wall" placed x (1, 0, 0) y (0, 1, 0) z (0, 0, 1) at (-91, -313, 232)
component "right hopper front wing" placed x (1, 0, 0) y (0, 1, 0) z (0, 0, 1) at (150, -199, 232)
component "right cross feed deck" placed x (1, 0, 0) y (0, 1, 0) z (0, 0, 1) at (-91, -199, 230)
component "right front elevator upright" placed x (1, 0, 0) y (0, 1, 0) z (0, 0, 1) at (183, -105, 111)
component "right rear elevator upright" placed x (1, 0, 0) y (0, 1, 0) z (0, 0, 1) at (319, -105, 113)
component "right elevator upper tie" placed x (0, 1, 0) y (0, 0, 1) z (1, 0, 0) at (181, -105, 637)
component "right inside lift belt" placed x (1, 0, 0) y (0, 1, 0) z (0, 0, 1) at (196, -91, 86)
component "right outside lift belt" placed x (1, 0, 0) y (0, 1, 0) z (0, 0, 1) at (301, -91, 86)
component "right lift shelf 1" placed x (1, 0, 0) y (0, 1, 0) z (0, 0, 1) at (244, -81, 99)
component "right lift shelf 2" placed x (1, 0, 0) y (0, 1, 0) z (0, 0, 1) at (244, -81, 258)
component "right lift shelf 3" placed x (1, 0, 0) y (0, 1, 0) z (0, 0, 1) at (244, -81, 417)
component "right lift shelf 4" placed x (1, 0, 0) y (0, 1, 0) z (0, 0, 1) at (244, -81, 576)
component "right intake ramp" placed x (0, 1, 0) y (0.257178, 0, 0.966364) z (0.966364, 0, -0.257178) at (213, -60, 48)
component "left hopper wall" placed x (1, 0, 0) y (0, 1, 0) z (0, 0, 1) at (-91, 313, 232)
component "left hopper front wing" placed x (1, 0, 0) y (0, 1, 0) z (0, 0, 1) at (150, 199, 232)
component "left cross feed deck" placed x (1, 0, 0) y (0, 1, 0) z (0, 0, 1) at (-91, 199, 230)
component "left front elevator upright" placed x (1, 0, 0) y (0, 1, 0) z (0, 0, 1) at (183, 105, 111)
component "left rear elevator upright" placed x (1, 0, 0) y (0, 1, 0) z (0, 0, 1) at (319, 105, 113)
component "left elevator upper tie" placed x (0, 1, 0) y (0, 0, 1) z (1, 0, 0) at (181, 105, 637)
component "left inside lift belt" placed x (1, 0, 0) y (0, 1, 0) z (0, 0, 1) at (196, 91, 86)
component "left outside lift belt" placed x (1, 0, 0) y (0, 1, 0) z (0, 0, 1) at (301, 91, 86)
component "left lift shelf 1" placed x (1, 0, 0) y (0, 1, 0) z (0, 0, 1) at (244, 81, 99)
component "left lift shelf 2" placed x (1, 0, 0) y (0, 1, 0) z (0, 0, 1) at (244, 81, 258)
component "left lift shelf 3" placed x (1, 0, 0) y (0, 1, 0) z (0, 0, 1) at (244, 81, 417)
component "left lift shelf 4" placed x (1, 0, 0) y (0, 1, 0) z (0, 0, 1) at (244, 81, 576)
component "left intake ramp" placed x (0, 1, 0) y (0.257178, 0, 0.966364) z (0.966364, 0, -0.257178) at (213, 60, 48)
component "central fore-aft feed deck" placed x (1, 0, 0) y (0, 1, 0) z (0, 0, 1) at (-90.5, 0, 230)
component "left lower lift stub shaft" placed x (-1, 0, 0) y (0, 0, 1) z (0, 1, 0) at (248, 88, 84)
component "right lower lift stub shaft" placed x (-1, 0, 0) y (0, 0, 1) z (0, 1, 0) at (248, -116, 84)
component "left upper lift stub shaft" placed x (-1, 0, 0) y (0, 0, 1) z (0, 1, 0) at (248, 88, 622)
component "right upper lift stub shaft" placed x (-1, 0, 0) y (0, 0, 1) z (0, 1, 0) at (248, -116, 622)
component "ground intake roller" placed x (-1, 0, 0) y (0, 0, 1) z (0, 1, 0) at (285.7664, -126, 342.4358)
component "right intake bearing arm" placed x (0.994522, 0, -0.104528) y (0, 1, 0) z (0.104528, 0, 0.994522) at (275, -150, 240)
component "right intake pivot plate" placed x (0, -1, 0) y (-0.17238, 0, 0.98503) z (-0.98503, 0, -0.17238) at (315, -150, 247)
component "right intake pivot axle" placed x (-1, 0, 0) y (0, 0, 1) z (0, 1, 0) at (275, -150, 240)
component "right intake journal" placed x (-1, 0, 0) y (0, 0, 1) z (0, 1, 0) at (285.7664, -150, 342.4358)
component "right upper head cheek" placed x (1, 0, 0) y (0, 1, 0) z (0, 0, 1) at (236, -150, 562)
component "left intake bearing arm" placed x (0.994522, 0, -0.104528) y (0, 1, 0) z (0.104528, 0, 0.994522) at (275, 150, 240)
component "left intake pivot plate" placed x (0, -1, 0) y (-0.17238, 0, 0.98503) z (-0.98503, 0, -0.17238) at (315, 150, 247)
component "left intake pivot axle" placed x (-1, 0, 0) y (0, 0, 1) z (0, 1, 0) at (275, 100, 240)
component "left intake journal" placed x (-1, 0, 0) y (0, 0, 1) z (0, 1, 0) at (285.7664, 126, 342.4358)
component "left upper head cheek" placed x (1, 0, 0) y (0, 1, 0) z (0, 0, 1) at (236, 150, 562)
component "right scoring wheel" placed x (0, -1, 0) y (0.5, 0, 0.866025) z (-0.866025, 0, 0.5) at (259.6506, -104, 588.5)
component "right scoring spindle" placed x (0, -1, 0) y (0.5, 0, 0.866025) z (-0.866025, 0, 0.5) at (269.1769, -104, 583)
component "right upper guide" placed x (0, 1, 0) y (-0.841019, 0, 0.541006) z (0.541006, 0, 0.841019) at (190, -80, 548)
component "right scoring bearing bridge -33" placed x (-1, 0, 0) y (0, 0, 1) z (0, 1, 0) at (266.5788, -146, 584.5)
component "right scoring bearing bridge 33" placed x (-1, 0, 0) y (0, 0, 1) z (0, 1, 0) at (209.4212, -146, 617.5)
component "left scoring wheel" placed x (0, -1, 0) y (0.5, 0, 0.866025) z (-0.866025, 0, 0.5) at (259.6506, 104, 588.5)
component "left scoring spindle" placed x (0, -1, 0) y (0.5, 0, 0.866025) z (-0.866025, 0, 0.5) at (269.1769, 104, 583)
component "left upper guide" placed x (0, 1, 0) y (-0.841019, 0, 0.541006) z (0.541006, 0, 0.841019) at (190, 80, 548)
component "left scoring bearing bridge -33" placed x (-1, 0, 0) y (0, 0, 1) z (0, 1, 0) at (266.5788, 104, 584.5)
component "left scoring bearing bridge 33" placed x (-1, 0, 0) y (0, 0, 1) z (0, 1, 0) at (209.4212, 104, 617.5)
component "left feed diverter pivot" placed x (-1, 0, 0) y (0, 0, 1) z (0, 1, 0) at (156, 76, 548)
component "right feed diverter pivot" placed x (-1, 0, 0) y (0, 0, 1) z (0, 1, 0) at (156, -100, 548)
component "feed diverter vane" placed x (1, 0, 0) y (0, 1, 0) z (0, 0, 1) at (156, 0, 548)
component "front left public wheel" placed x (-1, 0, 0) y (0, 0, 1) z (0, 1, 0) at (268, 255, 38.1)
component "front left public drive housing" placed x (1, 0, 0) y (0, 1, 0) z (0, 0, 1) at (268, 268, 70)
component "front left public motor reserve" placed x (1, 0, 0) y (0, 1, 0) z (0, 0, 1) at (268, 268, 115)
component "front right public wheel" placed x (-1, 0, 0) y (0, 0, 1) z (0, 1, 0) at (268, -281, 38.1)
component "front right public drive housing" placed x (1, 0, 0) y (0, 1, 0) z (0, 0, 1) at (268, -268, 70)
component "front right public motor reserve" placed x (1, 0, 0) y (0, 1, 0) z (0, 0, 1) at (268, -268, 115)
component "rear left public wheel" placed x (-1, 0, 0) y (0, 0, 1) z (0, 1, 0) at (-268, 255, 38.1)
component "rear left public drive housing" placed x (1, 0, 0) y (0, 1, 0) z (0, 0, 1) at (-268, 268, 70)
component "rear left public motor reserve" placed x (1, 0, 0) y (0, 1, 0) z (0, 0, 1) at (-268, 268, 115)
component "rear right public wheel" placed x (-1, 0, 0) y (0, 0, 1) z (0, 1, 0) at (-268, -281, 38.1)
component "rear right public drive housing" placed x (1, 0, 0) y (0, 1, 0) z (0, 0, 1) at (-268, -268, 70)
component "rear right public motor reserve" placed x (1, 0, 0) y (0, 1, 0) z (0, 0, 1) at (-268, -268, 115)
component "right public scoring motor envelope" placed x (0, -1, 0) y (0.5, 0, 0.866025) z (-0.866025, 0, 0.5) at (213.7513, -104, 615)
component "left public scoring motor envelope" placed x (0, -1, 0) y (0.5, 0, 0.866025) z (-0.866025, 0, 0.5) at (213.7513, 104, 615)
component "rear lift custody gate" placed x (1, 0, 0) y (0, 1, 0) z (0, 0, 1) at (169, 0, 134)
component "front lift custody guide" placed x (1, 0, 0) y (0, 1, 0) z (0, 0, 1) at (329, 0, 221)
component "left mast" placed x (1, 0, 0) y (0, 1, 0) z (0, 0, 1) at (-180, 326, 114.8)
component "left aft mast" placed x (1, 0, 0) y (0, 1, 0) z (0, 0, 1) at (-280, 326, 114.8)
component "left upper bearing plate" placed x (1, 0, 0) y (0, 1, 0) z (0, 0, 1) at (-230, 317, 744)
component "left lower bearing plate" placed x (1, 0, 0) y (0, 1, 0) z (0, 0, 1) at (-240, 313.5, 551)
component "left lead screw envelope" placed x (1, 0, 0) y (0, 1, 0) z (0, 0, 1) at (-240, 305, 557)
component "left lift motor envelope" placed x (1, 0, 0) y (0, 1, 0) z (0, 0, 1) at (-240, 258, 577)
component "left reduction envelope" placed x (1, 0, 0) y (0, 1, 0) z (0, 0, 1) at (-240, 280, 557)
component "left driven nut" placed x (1, 0, 0) y (0, 1, 0) z (0, 0, 1) at (-240, 305.5, 711)
component "left nut link" placed x (1, 0, 0) y (0, 1, 0) z (0, 0, 1) at (-240, 306, 701)
component "left crosshead cheek" placed x (1, 0, 0) y (0, 1, 0) z (0, 0, 1) at (-204.5, 303.5, 687)